SpeakerWallMount (Autodesk Fusion 360 design; units mm, degrees)
Autodesk Fusion 360 part; units mm, degrees
sketch "Sketch1" plane through (0, 0, 0) normal (0, 0, 1) x (1, 0, 0)
sketch "Sketch2" plane through (0, 0, 0) normal (0, 0, 1) x (1, 0, 0)
  arc A0 (-6, 28) -> (-46, 28) centre (-26, -57.7256) ccw
  arc A1 (6, 20) -> (-6, 28) centre (-12, 6) ccw
  arc A2 (12, 6) -> (6, 20) centre (-30.4109, -3.8904) ccw
  arc A3 (14.5091, -6.0045) -> (12, 6) centre (-248.5429, -54.7219) ccw
  arc A4 (15.4799, -16.007) -> (14.5091, -6.0045) centre (-216.6771, -33.4904) ccw
  arc A5 (16.312, -26.0095) -> (15.4799, -16.007) centre (-172.1636, -36.6527) ccw
  arc A6 (16.8789, -35.9513) -> (16.312, -26.0095) centre (-4614.5393, -295.0399) ccw
  arc A7 (13.5713, -39.9766) -> (16.8789, -35.9513) centre (11.4457, -34.8584) ccw
  arc A8 (-22, -48) -> (13.5713, -39.9766) centre (-28.2088, 62.3895) ccw
  arc A9 (-64.689, -40.8512) -> (-22, -48) centre (-28.9887, 41.3002) ccw
  arc A10 (-67.1809, -36.7547) -> (-64.689, -40.8512) centre (-62.5049, -36.7165) ccw
  arc A11 (-66, -14) -> (-67.1809, -36.7547) centre (3380.6428, -204.2809) ccw
  arc A12 (-64, 0) -> (-66, -14) centre (120.5526, -33.5075) ccw
  arc A13 (-60.6792, 12.035) -> (-64, 0) centre (20.6372, -16.8783) ccw
  arc A14 (-56.471, 19.9924) -> (-60.6792, 12.035) centre (-30.377, 1.1013) ccw
  arc A15 (-46, 28) -> (-56.471, 19.9924) centre (-35.8313, 3.8533) ccw
extrude "Extrude1" add sketch "Sketch2" along normal blind 3
fillet "Fillet1" radius 15 1 edges at (-46, 28, 1.5)
fillet "Fillet2" radius 5 1 edges at (16.8789, -35.9513, 1.5)
fillet "Fillet3" radius 2 1 edges at (-67.1809, -36.7547, 1.5)
fillet "Fillet4" radius 28.25 1 edges at (14.5091, -6.0045, 1.5)
sketch "Sketch3" plane through (0, 0, 0) normal (0, 1, 0) x (1, 0, 0)
  line L0 (10.0035, -21.4807) -> (-10.0035, -21.4807)
  line L1 (-10.0035, -21.4807) -> (-10.0035, 21.4807)
  line L2 (-10.0035, 21.4807) -> (10.0035, 21.4807)
  line L3 (10.0035, 21.4807) -> (10.0035, -21.4807)
  line L4 (10.0035, -21.4807) -> (-10.0035, 21.4807) construction
  line L5 (-10.0035, -21.4807) -> (10.0035, 21.4807) construction
  constraint perpendicular L0 L1
  constraint parallel L0 L2
  constraint parallel L1 L3
  constraint horizontal L0
  constraint coincident L4 origin
  constraint coincident L5 origin
ref_plane "WorkPlane1" through (0, 30, 0) normal (0, 1, 0) x (1, 0, 0)
sketch "Sketch4" plane through (0, 30, 0) normal (0, 1, 0) x (1, 0, 0)
  line L0 (-44.2509, 0) -> (-6, 0)
  line L1 (-67.1778, 0) -> (-25.1255, 0)
  line L2 (-67.1778, 0) -> (-25.1255, 0)
  line L3 (-25.1255, 0) -> (-25.1255, 4.4505)
  line L4 (-25.1255, 4.4505) -> (-67.1778, 4.4505)
  line L5 (-67.1778, 4.4505) -> (-67.1778, 0)
  line L6 (-25.1255, 0) -> (-25.1255, -40)
  line L7 (-17.6255, -39.8004) -> (-32.6255, -39.8004)
  line L8 (-32.6255, -39.8004) -> (-32.6255, -0.1996)
  line L9 (-32.6255, -0.1996) -> (-17.6255, -0.1996)
  line L10 (-17.6255, -0.1996) -> (-17.6255, -39.8004)
  line L11 (-17.6255, -39.8004) -> (-32.6255, -0.1996) construction
  line L12 (-32.6255, -39.8004) -> (-17.6255, -0.1996) construction
  point P0 (-67.1778, 0)
  point P1 (-25.1255, -20)
  dimension "d8" = 40
  dimension "d9" = 15
  constraint coincident P0 L1.start
  constraint midpoint L0 L1.end
  constraint horizontal L2
  constraint vertical L3
  constraint horizontal L4
  constraint vertical L5
  constraint perpendicular L7 L8
  constraint parallel L7 L9
  constraint parallel L8 L10
  constraint horizontal L7
  constraint coincident L11 P1
  constraint coincident L12 P1
  constraint midpoint L6 P1
  constraint perpendicular L0 L6
  measures "d8" distance of L1.end L6.end
  measures "d9" distance of L8.end L9.end
extrude "Extrude2" add sketch "Sketch4" along normal blind 3 contours L6 L7 L9 L10 | L6 L7 L8 L9
sketch "Sketch5" plane through (0, 33, 0) normal (0, 1, 0) x (-1, 0, 0)
  line L0 (17.6255, 0.1996) -> (32.6255, 0.1996)
  line L1 (32.6255, 0.1996) -> (32.6255, 39.8004)
  line L2 (32.6255, 39.8004) -> (17.6255, 39.8004)
  line L3 (17.6255, 39.8004) -> (17.6255, 0.1996)
  line L4 (25.1255, 39.8004) -> (25.1255, 29.8004)
  line L5 (25.1255, 39.8004) -> (25.1255, 34.8004)
  dimension "d20" = 10
  dimension "d21" = 5
  constraint midpoint L2 L4.start
  measures "d20" distance of L4.start L4.end
  measures "d21" distance of L4.start L5.end
sketch "Sketch8" plane through (0, 0, 0.1996) normal (0, 0, -1) x (-1, 0, 0)
  arc A0 (32.6255, 30.0524) -> (18.7132, 30) centre (26, -57.7256) ccw
  line L0 (32.6255, 30.0524) -> (32.6255, 33)
  line L1 (32.6255, 33) -> (17.6255, 33)
  line L2 (17.6255, 33) -> (17.6255, 30)
  line L3 (17.6255, 30) -> (18.7132, 30)
extrude "Extrude5" add sketch "Sketch8" along normal blind 0.2
sketch "Sketch9" plane through (0, 0, -0.0004) normal (0, 0, -1) x (-1, 0, 0)
  line L0 (32.6255, 30.0524) -> (32.6255, 33)
  line L1 (32.6255, 33) -> (17.6255, 33)
  line L2 (17.6255, 33) -> (17.6255, 30)
  line L3 (17.6255, 30) -> (18.7132, 30)
  arc A0 (32.6255, 30.0524) -> (18.7132, 30) centre (26, -57.7256) ccw
  line L4 (17.6255, 30) -> (17.6255, 29.6732)
  line L5 (17.6255, 29.6732) -> (18.8906, 29.7837)
  line L6 (18.8906, 29.7837) -> (18.7218, 30.1349)
  constraint coincident L2.end L3.start
  constraint perpendicular L3 L4
extrude "Extrude6" add sketch "Sketch9" against normal blind 3 contours L3 A0 L4 L5 L6
sketch "Sketch10" plane through (0, 0, 0) normal (0, 0, -1) x (-1, 0, 0)
  line L0 (18.7838, 30.0058) -> (18.8906, 29.7837)
  line L1 (18.8906, 29.7837) -> (17.6255, 29.6732)
  line L2 (17.6255, 29.6732) -> (17.6255, 29.9029)
  arc A0 (17.6255, 29.9029) -> (6, 28) centre (26, -57.7256) ccw
  arc A1 (6, 28) -> (-6, 20) centre (12, 6) ccw
  arc A2 (-6, 20) -> (-12, 6) centre (30.4109, -3.8904) ccw
  arc A3 (-12, 6) -> (-14.3199, -4.9939) centre (248.5429, -54.7219) ccw
  arc A4 (-14.3199, -4.9939) -> (-14.6293, -7.0349) centre (13.4377, -10.245) ccw
  arc A5 (-14.6293, -7.0349) -> (-15.4799, -16.007) centre (216.6771, -33.4904) ccw
  arc A6 (-15.4799, -16.007) -> (-16.312, -26.0095) centre (172.1636, -36.6527) ccw
  arc A7 (-16.312, -26.0095) -> (-16.8233, -34.9592) centre (4614.5393, -295.0399) ccw
  arc A8 (-16.8233, -34.9592) -> (-15.3867, -38.7549) centre (-11.8311, -35.2395) ccw
  arc A9 (-15.3867, -38.7549) -> (-13.5713, -39.9766) centre (-11.4457, -34.8584) ccw
  arc A10 (-13.5713, -39.9766) -> (22, -48) centre (28.2088, 62.3895) ccw
  arc A11 (22, -48) -> (64.689, -40.8512) centre (28.9887, 41.3002) ccw
  arc A12 (64.689, -40.8512) -> (67.1794, -36.8401) centre (62.5049, -36.7165) ccw
  arc A13 (67.1794, -36.8401) -> (67.1778, -36.6901) centre (65.1801, -36.7872) ccw
  arc A14 (67.1778, -36.6901) -> (66, -14) centre (-3380.6428, -204.2809) ccw
  arc A15 (66, -14) -> (64, 0) centre (-120.5526, -33.5075) ccw
  arc A16 (64, 0) -> (60.6792, 12.035) centre (-20.6372, -16.8783) ccw
  arc A17 (60.6792, 12.035) -> (56.471, 19.9924) centre (30.377, 1.1013) ccw
  arc A18 (56.471, 19.9924) -> (48.2518, 26.9227) centre (35.8313, 3.8533) ccw
  arc A19 (48.2518, 26.9227) -> (44.2509, 28.3893) centre (41.141, 13.7153) ccw
  arc A20 (44.2509, 28.3893) -> (32.6255, 30.0524) centre (26, -57.7256) ccw
  arc A21 (32.6255, 30.0524) -> (18.7838, 30.0058) centre (26, -57.7256) ccw
  line L3 (32.6255, 33) -> (17.6255, 33)
  line L4 (17.6255, 33) -> (25.1255, 33)
  line L5 (25.1255, 33) -> (27.6255, 33)
  line L6 (27.6255, 33) -> (27.6255, 20)
  line L7 (27.6255, 20) -> (25.1255, 20)
  line L8 (25.1255, 20) -> (25.1255, 33)
  line L9 (25.1255, 20) -> (22.6255, 20)
  line L10 (22.6255, 20) -> (22.6255, 33)
  line L11 (22.6255, 33) -> (25.1255, 33)
  line L12 (25.1255, 33) -> (25.1255, 20)
  point P0 (17.6255, 33)
  dimension "d28" = 13
  dimension "d29" = 2.5
  dimension "d30" = 2.5
  constraint coincident P0 L3.end
  constraint midpoint L3 L4.end
  constraint horizontal L5
  constraint vertical L6
  constraint horizontal L7
  constraint vertical L8
  constraint horizontal L9
  constraint vertical L10
  constraint horizontal L11
  constraint vertical L12
  measures "d28" distance of L4.end L7.end
  measures "d29" distance of L4.end L5.end
  measures "d30" distance of L7.end L9.end
extrude "Extrude7" cut sketch "Sketch10" against normal blind 10 contours A21 L3 L4 L8 L10 L11 L12 | A21 L8 L9 L10 L12 | A21 L3 L5 L6 L8 L12 | A21 L6 L7 L8 L12
sketch "Sketch11" plane through (0, 0, 0) normal (0, 0, 1) x (1, 0, 0)
  arc A0 (-22.6255, 30.2374) -> (-27.6255, 30.2871) centre (-26, -57.7256) ccw
  line L0 (-22.6255, 30.2374) -> (-22.6255, 33)
  line L1 (-22.6255, 33) -> (-27.6255, 33)
  line L2 (-27.6255, 33) -> (-27.6255, 30.2871)
extrude "Extrude8" cut sketch "Sketch11" against normal blind 1
sketch "Sketch12" plane through (0, 0, 0) normal (0, 0, -1) x (-1, 0, 0)
  line L0 (22.6255, 20) -> (22.6255, 30.2374)
  arc A0 (22.6255, 30.2374) -> (18.7838, 30.0058) centre (26, -57.7256) ccw
  line L1 (18.7838, 30.0058) -> (18.8906, 29.7837)
  line L2 (18.8906, 29.7837) -> (17.6255, 29.6732)
  line L3 (17.6255, 29.6732) -> (17.6255, 29.9029)
  arc A1 (17.6255, 29.9029) -> (6, 28) centre (26, -57.7256) ccw
  arc A2 (6, 28) -> (-6, 20) centre (12, 6) ccw
  arc A3 (-6, 20) -> (-12, 6) centre (30.4109, -3.8904) ccw
  arc A4 (-12, 6) -> (-14.3199, -4.9939) centre (248.5429, -54.7219) ccw
  arc A5 (-14.3199, -4.9939) -> (-14.6293, -7.0349) centre (13.4377, -10.245) ccw
  arc A6 (-14.6293, -7.0349) -> (-15.4799, -16.007) centre (216.6771, -33.4904) ccw
  arc A7 (-15.4799, -16.007) -> (-16.312, -26.0095) centre (172.1636, -36.6527) ccw
  arc A8 (-16.312, -26.0095) -> (-16.8233, -34.9592) centre (4614.5393, -295.0399) ccw
  arc A9 (-16.8233, -34.9592) -> (-15.3867, -38.7549) centre (-11.8311, -35.2395) ccw
  arc A10 (-15.3867, -38.7549) -> (-13.5713, -39.9766) centre (-11.4457, -34.8584) ccw
  arc A11 (-13.5713, -39.9766) -> (22, -48) centre (28.2088, 62.3895) ccw
  arc A12 (22, -48) -> (64.689, -40.8512) centre (28.9887, 41.3002) ccw
  arc A13 (64.689, -40.8512) -> (67.1794, -36.8401) centre (62.5049, -36.7165) ccw
  arc A14 (67.1794, -36.8401) -> (67.1778, -36.6901) centre (65.1801, -36.7872) ccw
  arc A15 (67.1778, -36.6901) -> (66, -14) centre (-3380.6428, -204.2809) ccw
  arc A16 (66, -14) -> (64, 0) centre (-120.5526, -33.5075) ccw
  arc A17 (64, 0) -> (60.6792, 12.035) centre (-20.6372, -16.8783) ccw
  arc A18 (60.6792, 12.035) -> (56.471, 19.9924) centre (30.377, 1.1013) ccw
  arc A19 (56.471, 19.9924) -> (48.2518, 26.9227) centre (35.8313, 3.8533) ccw
  arc A20 (48.2518, 26.9227) -> (44.2509, 28.3893) centre (41.141, 13.7153) ccw
  arc A21 (44.2509, 28.3893) -> (32.6255, 30.0524) centre (26, -57.7256) ccw
  arc A22 (32.6255, 30.0524) -> (27.6255, 30.2871) centre (26, -57.7256) ccw
  line L4 (27.6255, 30.2871) -> (27.6255, 20)
  line L5 (27.6255, 20) -> (22.6255, 20)
  line L6 (12.5439, 36.6664) -> (40.2124, 36.6664)
  line L7 (40.2124, 36.6664) -> (40.2124, 18.7394)
  line L8 (40.2124, 18.7394) -> (12.5439, 18.7394)
  line L9 (12.5439, 18.7394) -> (12.5439, 36.6664)
  constraint horizontal L6
  constraint vertical L7
  constraint horizontal L8
  constraint vertical L9
extrude "Extrude9" cut sketch "Sketch12" along normal blind 5 contours L0 A0 L1 L2 L3 A1 A21 A22 L4 L5 L7 L8 L9 | L0 A0 L1 L2 L3 A1 A21 A22 L4 L5 L6 L7 L9
sketch "Sketch13" plane through (0, 33, 0) normal (0, 1, 0) x (-1, 0, 0)
  line L0 (27.6255, 0) -> (32.6255, 0)
  line L1 (32.6255, 0) -> (32.6255, 39.8004)
  line L2 (32.6255, 39.8004) -> (17.6255, 39.8004)
  line L3 (17.6255, 39.8004) -> (17.6255, 0)
  line L4 (17.6255, 0) -> (22.6255, 0)
  line L5 (22.6255, 0) -> (22.6255, 10)
  line L6 (22.6255, 10) -> (27.6255, 10)
  line L7 (27.6255, 10) -> (27.6255, 0)
  line L8 (25.1255, 39.8004) -> (25.1255, 30.8004)
  line L9 (25.1255, 30.8004) -> (28.8755, 30.8004)
  line L10 (25.1255, 30.8004) -> (21.3755, 30.8004)
  circle A0 centre (28.8755, 30.8004) radius 1.675
  circle A1 centre (21.3755, 30.8004) radius 1.675
  dimension "d37" = 9
  dimension "d38" = 3.75
  dimension "d39" = 3.75
  dimension "d40" = 3.35
  dimension "d41" = 3.35
  constraint midpoint L2 L8.start
  constraint coincident L9.end A0.centre
  constraint coincident L10.end A1.centre
  measures "d37" distance of L8.start L8.end
  measures "d38" distance of L8.end L9.end
  measures "d39" distance of L8.end L10.end
  measures "d40" diameter of A0
  measures "d41" diameter of A1
ref_plane "WorkPlane2" through (-25.1255, 32, 19.9002) normal (0, 1, 0) x (-1, 0, 0)
sketch "Sketch14" plane through (-25.1255, 32, 19.9002) normal (0, 1, 0) x (1, 0, 0)
  circle A0 centre (-3.75, -10.9002) radius 1.675
  circle A1 centre (-3.75, -10.9002) radius 1.675
  circle A2 centre (3.75, -10.9002) radius 1.675
  circle A3 centre (3.75, -10.9002) radius 1.675
  point P0 (-3.75, -10.9002)
  point P1 (3.75, -10.9002)
  constraint coincident P0 A0.centre
  constraint coincident P1 A2.centre
sketch "Sketch15" plane through (0, 30, 0) normal (0, -1, 0) x (1, 0, 0)
  line L0 (-27.6255, 3) -> (-27.6255, 10)
  line L1 (-27.6255, 10) -> (-22.6255, 10)
  line L2 (-22.6255, 10) -> (-22.6255, 3)
  line L3 (-22.6255, 3) -> (-18.7132, 3)
  line L4 (-18.7132, 3) -> (-18.7132, 2.9996)
  line L5 (-18.7132, 2.9996) -> (-17.6255, 2.9996)
  line L6 (-17.6255, 2.9996) -> (-17.6255, 39.8004)
  line L7 (-17.6255, 39.8004) -> (-32.6255, 39.8004)
  line L8 (-32.6255, 39.8004) -> (-32.6255, 3)
  line L9 (-32.6255, 3) -> (-27.6255, 3)
  circle A0 centre (-28.8755, 30.8004) radius 3.35
  circle A1 centre (-21.3755, 30.8004) radius 3.35
  point P0 (-28.8755, 30.8004)
  point P1 (-21.3755, 30.8004)
  dimension "d43" = 6.7
  dimension "d44" = 6.7
  constraint coincident P0 A0.centre
  constraint coincident P1 A1.centre
  measures "d43" diameter of A0
  measures "d44" diameter of A1
loft "Loft1" cut profiles "Sketch15", "Sketch14" section 1 contours A1 section 2 contours A2 A3
loft "Loft2" cut profiles "Sketch15", "Sketch14" section 1 contours A0 section 2 contours A0 A1
extrude "Extrude10" cut sketch "Sketch13" against normal blind 3.5 contours A0 | A1
chamfer "Chamfer1" distance 2 angle 45 1 edges at (-25.1255, 20, 3) tangent chain off
fillet "Fillet5" radius 1 2 edges at (-25.1255, 20, 1) (-25.1255, 20, 0)
chamfer "Chamfer4" distance 3.097 angle 45 1 edges at (-17.6255, 29.9029, 1.4998) tangent chain off
sketch "Sketch16" plane through (0, 0, 2.9996) normal (0, 0, 1) x (1, 0, 0)
  arc A0 (-14.5482, 29.554) -> (-18.7132, 30) centre (-26, -57.7256) ccw
  line L0 (-14.9464, 30) -> (-18.7132, 30)
  line L1 (-14.9464, 30) -> (-83.8895, 30)
  line L2 (-83.8895, 30) -> (-83.8895, -56.8113)
  line L3 (-83.8895, -56.8113) -> (-14.9464, -56.8113)
  line L4 (-14.9464, -56.8113) -> (-14.9464, 30)
  line L5 (-14.9464, 30) -> (42.4873, 30)
  line L6 (42.4873, 30) -> (42.4873, -57.4827)
  line L7 (42.4873, -57.4827) -> (-14.9464, -57.4827)
  line L8 (-14.9464, -57.4827) -> (-14.9464, 30)
  line L9 (-14.9464, 30) -> (-57.0326, 30)
  line L10 (-57.0326, 30) -> (-57.0326, 45.3943)
  line L11 (-57.0326, 45.3943) -> (-14.9464, 45.3943)
  line L12 (-14.9464, 45.3943) -> (-14.9464, 30)
  line L13 (-14.9464, 30) -> (-10.3421, 30)
  line L14 (-10.3421, 30) -> (-10.3421, 35.833)
  line L15 (-10.3421, 35.833) -> (-14.9464, 35.833)
  line L16 (-14.9464, 35.833) -> (-14.9464, 30)
  line L17 (-14.5482, 29.554) -> (-14.9464, 30)
  line L18 (-17.6255, 32.9999) -> (-7.5243, 32.9999)
  line L19 (-7.5243, 32.9999) -> (-7.5243, 26.8668)
  line L20 (-7.5243, 26.8668) -> (-17.6255, 26.8668)
  line L21 (-17.6255, 26.8668) -> (-17.6255, 32.9999)
  point P0 (-17.6255, 32.9999)
  constraint horizontal L1
  constraint vertical L2
  constraint horizontal L3
  constraint vertical L4
  constraint coincident L0.start L1.start
  constraint horizontal L5
  constraint vertical L6
  constraint horizontal L7
  constraint vertical L8
  constraint horizontal L9
  constraint vertical L10
  constraint horizontal L11
  constraint vertical L12
  constraint horizontal L13
  constraint vertical L14
  constraint horizontal L15
  constraint vertical L16
  constraint horizontal L18
  constraint vertical L19
  constraint horizontal L20
  constraint vertical L21
  constraint coincident P0 L18.start
extrude "Extrude12" cut sketch "Sketch16" along normal blind 54 contours A0 L4 L5 L8 L13 L17 L19 L20 | A0 L4 L8 L17 | A0 L4 L8 L20 L21 | A0 L0 L1 L4 L8 L9 L21 | L5 L12 L13 L14 L16 L18 | L0 L1 L9 L12 L16 L18 L21 | A0 L1 L2 L3 L4 L8 L9 L20 L21 | A0 L0 L1 L9 L21 | L4 L5 L6 L7 L8 L19 L20
chamfer "Chamfer5" distance 2.947 angle 45 1 edges at (-32.6255, 30.0524, 1.5) tangent chain off
sketch "Sketch17" plane through (0, 0, 0) normal (0, 0, -1) x (-1, 0, 0)
  line L0 (27.6255, 33) -> (27.6255, 18.5858)
  line L1 (27.6255, 18.5858) -> (22.6255, 18.5858)
  line L2 (22.6255, 18.5858) -> (22.6255, 33)
  line L3 (22.6255, 33) -> (17.6255, 33)
  line L4 (17.6255, 33) -> (17.6255, 32.9999)
  line L5 (17.6255, 32.9999) -> (14.5482, 29.554)
  arc A0 (14.5482, 29.554) -> (6, 28) centre (26, -57.7256) ccw
  arc A1 (6, 28) -> (-6, 20) centre (12, 6) ccw
  arc A2 (-6, 20) -> (-12, 6) centre (30.4109, -3.8904) ccw
  arc A3 (-12, 6) -> (-14.3199, -4.9939) centre (248.5429, -54.7219) ccw
  arc A4 (-14.3199, -4.9939) -> (-14.6293, -7.0349) centre (13.4377, -10.245) ccw
  arc A5 (-14.6293, -7.0349) -> (-15.4799, -16.007) centre (216.6771, -33.4904) ccw
  arc A6 (-15.4799, -16.007) -> (-16.312, -26.0095) centre (172.1636, -36.6527) ccw
  arc A7 (-16.312, -26.0095) -> (-16.8233, -34.9592) centre (4614.5393, -295.0399) ccw
  arc A8 (-16.8233, -34.9592) -> (-15.3867, -38.7549) centre (-11.8311, -35.2395) ccw
  arc A9 (-15.3867, -38.7549) -> (-13.5713, -39.9766) centre (-11.4457, -34.8584) ccw
  arc A10 (-13.5713, -39.9766) -> (22, -48) centre (28.2088, 62.3895) ccw
  arc A11 (22, -48) -> (64.689, -40.8512) centre (28.9887, 41.3002) ccw
  arc A12 (64.689, -40.8512) -> (67.1794, -36.8401) centre (62.5049, -36.7165) ccw
  arc A13 (67.1794, -36.8401) -> (67.1778, -36.6901) centre (65.1801, -36.7872) ccw
  arc A14 (67.1778, -36.6901) -> (66, -14) centre (-3380.6428, -204.2809) ccw
  arc A15 (66, -14) -> (64, 0) centre (-120.5526, -33.5075) ccw
  arc A16 (64, 0) -> (60.6792, 12.035) centre (-20.6372, -16.8783) ccw
  arc A17 (60.6792, 12.035) -> (56.471, 19.9924) centre (30.377, 1.1013) ccw
  arc A18 (56.471, 19.9924) -> (48.2518, 26.9227) centre (35.8313, 3.8533) ccw
  arc A19 (48.2518, 26.9227) -> (44.2509, 28.3893) centre (41.141, 13.7153) ccw
  arc A20 (44.2509, 28.3893) -> (35.56, 29.7815) centre (26, -57.7256) ccw
  line L6 (35.56, 29.7815) -> (32.6255, 32.9994)
  line L7 (32.6255, 32.9994) -> (32.6255, 33)
  line L8 (32.6255, 33) -> (27.6255, 33)
  line L9 (17.6255, 32.9999) -> (32.6255, 33)
  line L10 (22.6255, 33) -> (27.6255, 33)
  line L11 (27.6255, 33) -> (27.6255, 13.4638)
  line L12 (27.6255, 13.4638) -> (22.6255, 13.4638)
  line L13 (22.6255, 13.4638) -> (22.6255, 33)
  constraint coincident L4.end L5.start
  constraint coincident L7.end L8.start
  constraint horizontal L10
  constraint vertical L11
  constraint horizontal L12
  constraint vertical L13
  constraint coincident L2.end L3.start
extrude "Extrude13" cut sketch "Sketch17" against normal blind 3 contours L0 L1 L2 L9 L10 L11 L13 | L1 L11 L12 L13
sketch "Sketch18" plane through (0, 13.4638, 0) normal (0, 1, 0) x (-1, 0, 0)
  line L0 (27.6255, 2.9996) -> (22.6255, 2.9996)
  line L1 (22.6255, 2.9996) -> (22.6255, 0)
  line L2 (22.6255, 0) -> (27.6255, 0)
  line L3 (27.6255, 0) -> (27.6255, 2.9996)
extrude "Extrude14" add sketch "Sketch18" along normal blind 19.536
sketch "Sketch19" plane through (0, 33, 0) normal (0, 1, 0) x (-1, 0, 0)
  circle A0 centre (21.3755, 30.8004) radius 1.675
  circle A1 centre (28.8755, 30.8004) radius 1.675
  line L0 (27.6255, 0) -> (32.6255, 0)
  line L1 (32.6255, 0) -> (32.6255, 39.8004)
  line L2 (32.6255, 39.8004) -> (17.6255, 39.8004)
  line L3 (17.6255, 39.8004) -> (17.6255, 0)
  line L4 (17.6255, 0) -> (22.6255, 0)
  line L5 (22.6255, 0) -> (22.6255, 10)
  line L6 (22.6255, 10) -> (27.6255, 10)
  line L7 (27.6255, 10) -> (27.6255, 0)
  line L8 (37.1534, -3.6636) -> (11.48, -3.6636)
  line L9 (11.48, -3.6636) -> (11.48, 43.8704)
  line L10 (11.48, 43.8704) -> (37.1534, 43.8704)
  line L11 (37.1534, 43.8704) -> (37.1534, -3.6636)
  constraint horizontal L8
  constraint vertical L9
  constraint horizontal L10
  constraint vertical L11
extrude "Extrude15" cut sketch "Sketch19" against normal blind 0.1 contours L0 L1 L2 L3 L4 L5 L6 L7 | L8 L9 L10 L11
sketch "Sketch20" plane through (0, 32.9, 0) normal (0, 1, 0) x (-1, 0, 0)
  line L0 (22.6255, 2.9996) -> (22.6255, 10)
  line L1 (22.6255, 10) -> (27.6255, 10)
  line L2 (27.6255, 10) -> (27.6255, 2.9996)
  line L3 (27.6255, 2.9996) -> (22.6255, 2.9996)
  line L4 (17.6255, 39.8004) -> (17.6255, 2.9996)
  line L5 (17.6255, 2.9996) -> (17.5363, 2.9996)
  line L6 (17.5363, 2.9996) -> (17.5363, 0)
  line L7 (17.5363, 0) -> (32.7161, 0)
  line L8 (32.7161, 0) -> (32.7161, 3)
  line L9 (32.7161, 3) -> (32.6255, 3)
  line L10 (32.6255, 3) -> (32.6255, 39.8004)
  line L11 (32.6255, 39.8004) -> (17.6255, 39.8004)
  circle A0 centre (28.8755, 30.8004) radius 1.675
  circle A1 centre (21.3755, 30.8004) radius 1.675
extrude "Extrude16" add sketch "Sketch20" along normal blind 0.1
sketch "Sketch21" plane through (0, 0, 10) normal (0, 0, -1) x (-1, 0, 0)
  line L0 (22.6255, 33) -> (22.6255, 30)
  line L1 (22.6255, 30) -> (27.6255, 30)
  line L2 (27.6255, 30) -> (27.6255, 33)
  line L3 (27.6255, 33) -> (22.6255, 33)
extrude "Extrude17" cut sketch "Sketch21" against normal blind 5
sketch "Sketch22" plane through (0, 0, 15) normal (0, 0, -1) x (-1, 0, 0)
  line L0 (27.6255, 33) -> (22.6255, 33)
  line L1 (22.6255, 33) -> (22.6255, 30)
  line L2 (22.6255, 30) -> (27.6255, 30)
  line L3 (27.6255, 30) -> (27.6255, 33)
  line L4 (25.3755, 30) -> (24.8755, 30)
  line L5 (24.8755, 30) -> (24.8755, 33)
  line L6 (24.8755, 33) -> (25.3755, 33)
  line L7 (25.3755, 33) -> (25.3755, 30)
  dimension "d67" = 3
  dimension "d68" = 0.5
  constraint perpendicular L4 L5
  constraint parallel L4 L6
  constraint parallel L5 L7
  constraint horizontal L4
  measures "d67" distance of L4.end L5.end
  measures "d68" distance of L5.end L6.end
extrude "Extrude18" cut sketch "Sketch22" against normal up to surface (24.8004 mm away) contours L0 L2 L4 L5 L6 L7
sketch "Sketch23" plane through (0, 33, 0) normal (0, 1, 0) x (-1, 0, 0)
  line L0 (24.8755, 15) -> (24.8755, 39.8004)
  line L1 (24.8755, 39.8004) -> (17.6255, 39.8004)
  line L2 (17.6255, 39.8004) -> (17.6255, 2.9996)
  line L3 (17.6255, 2.9996) -> (17.5363, 2.9996)
  line L4 (17.5363, 2.9996) -> (17.5363, 0)
  line L5 (17.5363, 0) -> (32.7161, 0)
  line L6 (32.7161, 0) -> (32.7161, 3)
  line L7 (32.7161, 3) -> (32.6255, 3)
  line L8 (32.6255, 3) -> (32.6255, 39.8004)
  line L9 (32.6255, 39.8004) -> (25.3755, 39.8004)
  line L10 (25.3755, 39.8004) -> (25.3755, 15)
  line L11 (25.3755, 15) -> (27.6255, 15)
  line L12 (27.6255, 15) -> (27.6255, 2.9996)
  line L13 (27.6255, 2.9996) -> (22.6255, 2.9996)
  line L14 (22.6255, 2.9996) -> (22.6255, 15)
  line L15 (22.6255, 15) -> (24.8755, 15)
  circle A0 centre (28.8755, 30.8004) radius 1.675
  circle A1 centre (21.3755, 30.8004) radius 1.675
extrude "Extrude19" add sketch "Sketch23" along normal blind 2
sketch "Sketch24" plane through (0, 35, 0) normal (0, 1, 0) x (-1, 0, 0)
  circle A0 centre (28.8755, 30.8004) radius 1.675
  circle A1 centre (21.3755, 30.8004) radius 1.675
  line L0 (22.6255, 15) -> (24.8755, 15)
  line L1 (24.8755, 15) -> (24.8755, 39.8004)
  line L2 (24.8755, 39.8004) -> (17.6255, 39.8004)
  line L3 (17.6255, 39.8004) -> (17.6255, 2.9996)
  line L4 (17.6255, 2.9996) -> (17.5363, 2.9996)
  line L5 (17.5363, 2.9996) -> (17.5363, 0)
  line L6 (17.5363, 0) -> (32.7161, 0)
  line L7 (32.7161, 0) -> (32.7161, 3)
  line L8 (32.7161, 3) -> (32.6255, 3)
  line L9 (32.6255, 3) -> (32.6255, 39.8004)
  line L10 (32.6255, 39.8004) -> (25.3755, 39.8004)
  line L11 (25.3755, 39.8004) -> (25.3755, 15)
  line L12 (25.3755, 15) -> (27.6255, 15)
  line L13 (27.6255, 15) -> (27.6255, 2.9996)
  line L14 (27.6255, 2.9996) -> (22.6255, 2.9996)
  line L15 (22.6255, 2.9996) -> (22.6255, 15)
  line L16 (25.1262, 0) -> (25.1255, 2.9996)
  line L17 (25.1258, 1.4998) -> (32.7161, 1.5)
  line L18 (25.1258, 1.4998) -> (17.5363, 1.4998)
  line L19 (22.6255, 3.6804) -> (27.6262, 3.6804)
  line L20 (27.6262, 3.6804) -> (27.6262, -0.6808)
  line L21 (27.6262, -0.6808) -> (22.6255, -0.6808)
  line L22 (22.6255, -0.6808) -> (22.6255, 3.6804)
  line L23 (22.6255, 3.6804) -> (27.6262, -0.6808) construction
  line L24 (27.6262, 3.6804) -> (22.6255, -0.6808) construction
  point P0 (25.1258, 1.4998)
  constraint midpoint L6 L16.start
  constraint midpoint L14 L16.end
  constraint midpoint L16 P0
  constraint midpoint L7 L17.end
  constraint midpoint L5 L18.end
  constraint perpendicular L19 L20
  constraint parallel L19 L21
  constraint parallel L20 L22
  constraint horizontal L19
  constraint coincident L15 L19.start
  constraint coincident L23 P0
  constraint coincident L24 P0
  constraint coincident P0 L17.start
extrude "Extrude20" cut sketch "Sketch24" against normal blind 4 contours L14 L16 L18 L22 | L13 L14 L16 L17 L19 L20 | L6 L16 L18 L22 | L6 L16 L17 L20
fillet "Fillet6" radius 1 2 edges at (-25.1255, 31, 2.9996) (-25.1258, 31, 0)
fillet "Fillet7" radius 3 2 edges at (-24.8755, 32.5, 39.8004) (-25.3755, 32.5, 39.8004)
chamfer "Chamfer6" distance 2.25 angle 45 2 edges at (-25.3755, 32.5, 15) (-24.8755, 32.5, 15) tangent chain off
